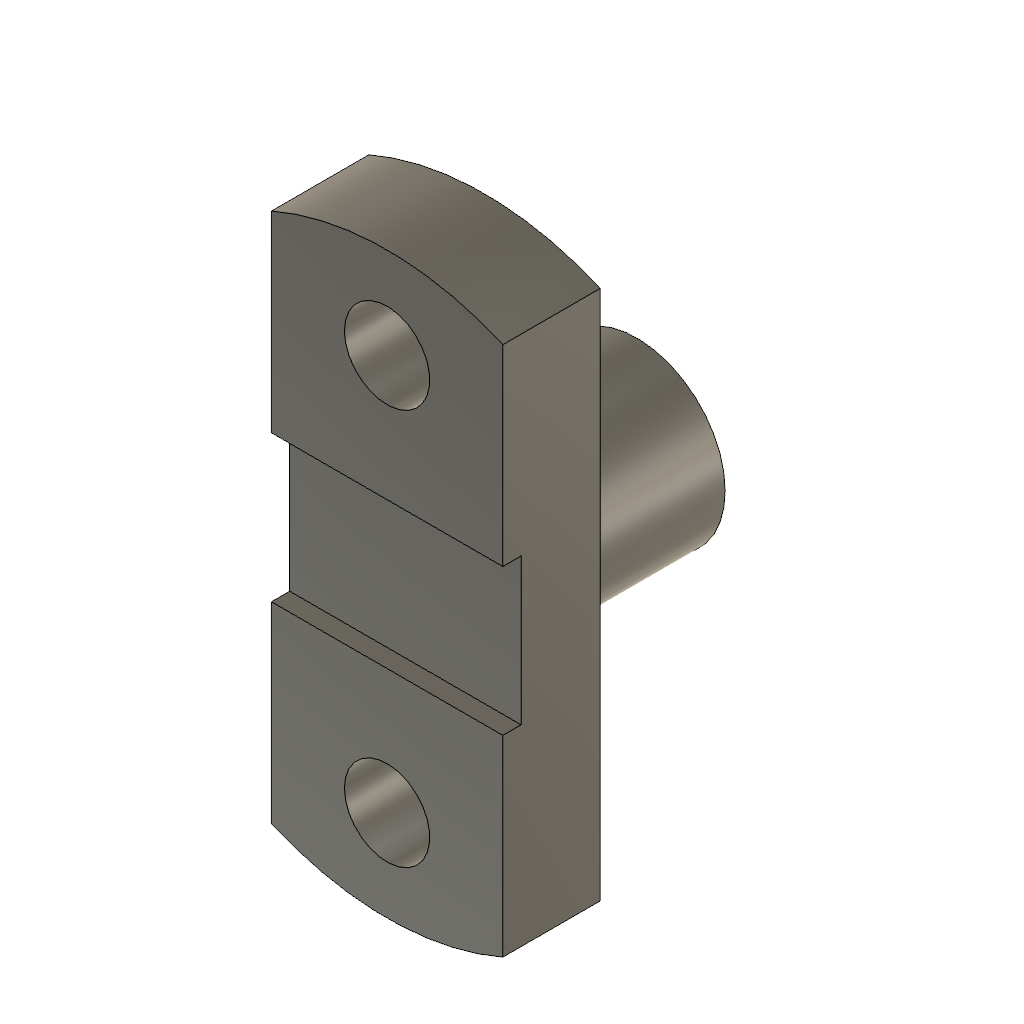
assembled one (Autodesk Fusion 360 archive; units mm, degrees)
design "rodend"
part number: 2026-10-08-14-04-04-450
Autodesk Fusion 360 part; units mm, degrees
sketch "Sketch1" plane through (0, 0, 0) normal (0, 1, 0) x (1, 0, 0)
  line L0 (0, 0) -> (76, 0)
  line L1 (76, 0) -> (76, -190)
  line L2 (76, -190) -> (0, -190)
  line L3 (0, -190) -> (0, 0)
  line L4 (0, -190) -> (38, -190)
  line L5 (38, -190) -> (38, -160)
  line L6 (38, -160) -> (0, -160)
  line L7 (0, -160) -> (0, -190)
  circle A0 centre (38, -160) radius 14
  line L8 (38, -160) -> (38, -30)
  circle A1 centre (38, -30) radius 14
  dimension "d1" = 76
  dimension "d2" = 190
  dimension "d3" = 38
  dimension "d4" = 30
  dimension "d5" = 28
  dimension "d6" = 130
  dimension "d7" = 28
  constraint horizontal L0
  constraint vertical L1
  constraint horizontal L2
  constraint vertical L3
  constraint coincident L0.start L3.end
  constraint horizontal L4
  constraint vertical L5
  constraint horizontal L6
  constraint vertical L7
  constraint coincident L5.end L6.start
  constraint perpendicular L6 L8
  constraint coincident L8.end A1.centre
  measures "d1" distance of L0.start L0.end
  measures "d2" distance of L0.start L2.end
  measures "d3" distance of L2.end L4.end
  measures "d4" distance of L2.end L6.end
  measures "d5" diameter of A0
  measures "d6" distance of L5.end L8.end
  measures "d7" diameter of A1
extrude "Extrude1" add sketch "Sketch1" along normal blind 32 contours L0 L1 L2 L3 L5 L6 A0 | L2 L3 L4 L5 L6 L7 A0
sketch "Sketch2" plane through (76, 0, 0) normal (1, 0, 0) x (0, 1, 0)
  line L0 (0, 190) -> (0, 0)
  line L1 (0, 0) -> (32, 0)
  line L2 (32, 0) -> (32, 190)
  line L3 (32, 190) -> (0, 190)
  line L4 (0, 190) -> (0, 95)
  line L5 (6, 71) -> (-6, 71)
  line L6 (-6, 71) -> (-6, 119)
  line L7 (-6, 119) -> (6, 119)
  line L8 (6, 119) -> (6, 71)
  line L9 (6, 71) -> (-6, 119) construction
  line L10 (-6, 71) -> (6, 119) construction
  point P0 (0, 95)
  dimension "d10" = 95
  dimension "d11" = 12
  dimension "d12" = 48
  constraint coincident L0.start L3.end
  constraint perpendicular L3 L4
  constraint horizontal L5
  constraint perpendicular L5 L6
  constraint parallel L5 L7
  constraint parallel L6 L8
  constraint coincident L9 P0
  constraint coincident L10 P0
  constraint coincident P0 L4.end
  measures "d10" distance of L0.start P0
  measures "d11" distance of L6.end L7.end
  measures "d12" distance of L5.end L6.end
extrude "Extrude2" cut sketch "Sketch2" against normal blind 170 contours L0 L4 L5 L7 L8
sketch "Sketch3" plane through (0, 32, 0) normal (0, 1, 0) x (-1, 0, 0)
  circle A0 centre (-38, 160) radius 14
  circle A1 centre (-38, 30) radius 14
  line L0 (0, 0) -> (0, 190)
  line L1 (0, 190) -> (-76, 190)
  line L2 (-76, 190) -> (-76, 0)
  line L3 (-76, 0) -> (0, 0)
  line L4 (-76, 190) -> (-38, 190)
  line L5 (-76, 95) -> (-76, 190)
  circle A2 centre (-38, 95) radius 29
  dimension "d15" = 38
  dimension "d16" = 95
  dimension "d17" = 58
  constraint horizontal L4
  constraint vertical L5
  constraint coincident L1.end L2.start
  measures "d15" distance of L1.end L4.end
  measures "d16" distance of L1.end L5.start
  measures "d17" diameter of A2
extrude "Extrude3" add sketch "Sketch3" along normal blind 50 contours A2
sketch "Sketch4" plane through (0, 0, 0) normal (0, -1, 0) x (1, 0, 0)
  line L0 (0, 119) -> (76, 119)
  line L1 (76, 119) -> (76, 190)
  line L2 (76, 190) -> (0, 190)
  line L3 (0, 190) -> (0, 119)
  circle A0 centre (38, 160) radius 14
  line L4 (0, 190) -> (38, 190)
  line L5 (38, 190) -> (38, 95)
  line L6 (38, 95) -> (0, 95)
  line L7 (0, 95) -> (0, 190)
  circle A1 centre (38, 95) radius 95
  dimension "d20" = 38
  dimension "d21" = 95
  dimension "d22" = 190
  constraint horizontal L4
  constraint vertical L5
  constraint horizontal L6
  constraint vertical L7
  constraint coincident L2.end L3.start
  constraint coincident L5.end L6.start
  measures "d20" distance of L2.end L4.end
  measures "d21" distance of L2.end L6.end
  measures "d22" diameter of A1
extrude "Extrude4" cut sketch "Sketch4" against normal blind 170 contours L2 L3 L4 L7 A1 | L1 L2 A1
sketch "Sketch5" plane through (0, 0, 0) normal (0, -1, 0) x (1, 0, 0)
  circle A0 centre (38, 30) radius 14
  line L0 (76, 71) -> (0, 71)
  line L1 (0, 71) -> (0, 0)
  line L2 (0, 0) -> (76, 0)
  line L3 (76, 0) -> (76, 71)
  line L4 (0, 0) -> (38, 0)
  line L5 (38, 0) -> (38, 95)
  line L6 (38, 95) -> (0, 95)
  line L7 (0, 95) -> (0, 0)
  circle A1 centre (38, 95) radius 95
  dimension "d25" = 38
  dimension "d26" = 95
  dimension "d27" = 190
  constraint horizontal L4
  constraint vertical L5
  constraint horizontal L6
  constraint vertical L7
  constraint coincident L1.end L2.start
  constraint coincident L5.end L6.start
  measures "d25" distance of L1.end L4.end
  measures "d26" distance of L1.end L6.end
  measures "d27" diameter of A1
extrude "Extrude5" cut sketch "Sketch5" against normal blind 490 contours L2 L3 A1 | L1 L2 L4 L7 A1

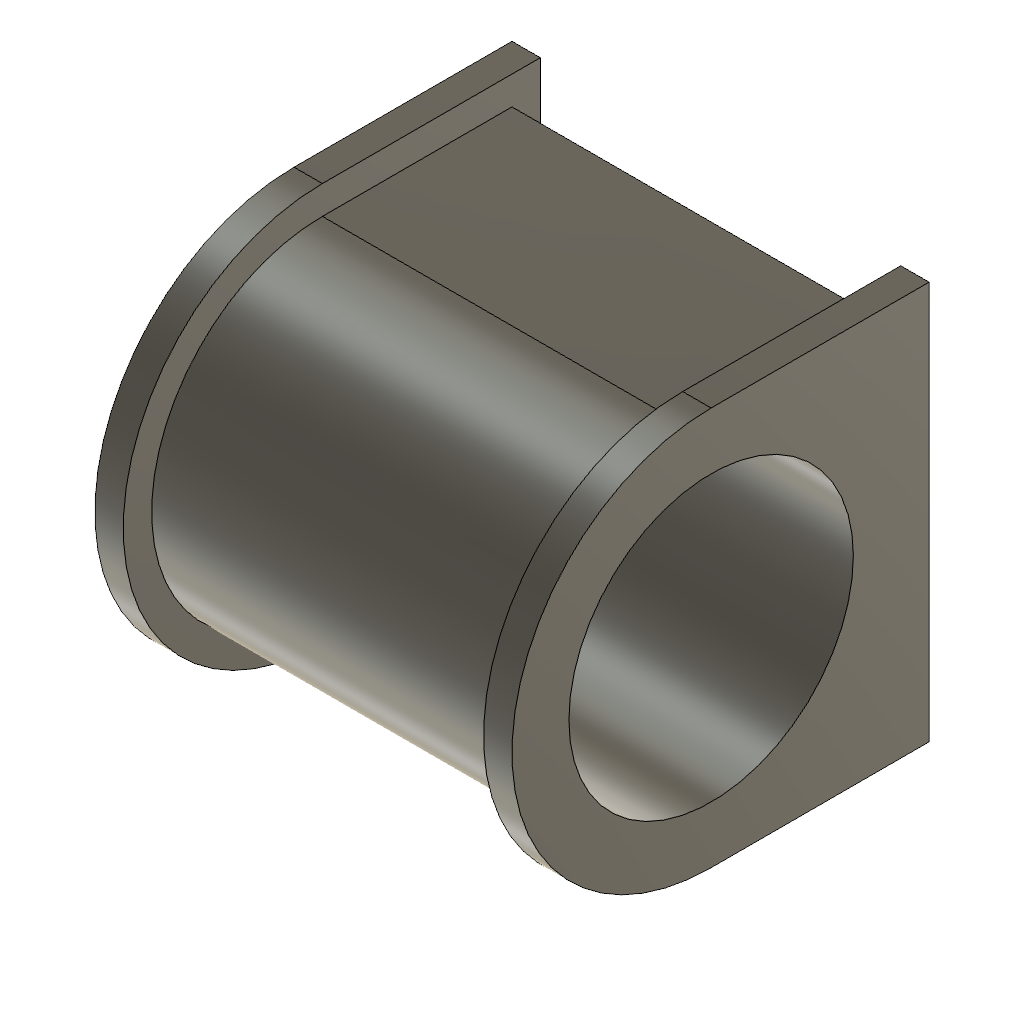
design "brasses"
part number: 2026-10-08-14-32-37-990
Autodesk Fusion 360 part; units mm, degrees
sketch "Sketch1" plane through (0, 0, 0) normal (1, 0, 0) x (0, 1, 0)
  circle A0 centre (0, 0) radius 30
  line L0 (0, 36) -> (40, 36)
  line L1 (0, 42) -> (46, 42)
  line L2 (0, -36) -> (40, -36)
  line L3 (0, -42) -> (46, -42)
  line L4 (40, 36) -> (40, -36)
  line L5 (46, 42) -> (46, -42)
  arc A1 (0, 36) -> (0, -36) centre (0, 0) ccw
  arc A2 (0, 42) -> (0, -42) centre (0, 0) ccw
  dimension "d1" = 60
  dimension "d2" = 72
  dimension "d3" = 84
  dimension "d4" = 40
  dimension "d5" = 46
  dimension "d6" = 40
  dimension "d7" = 46
  constraint coincident A0.centre A1.centre
  constraint horizontal L0
  constraint horizontal L1
  constraint horizontal L2
  constraint horizontal L3
  constraint tangent L0 A1
  constraint tangent L1 A2
  constraint tangent L2 A1
  constraint tangent L3 A2
  measures "d1" diameter of A0
  measures "d2" diameter of A1
  measures "d3" diameter of A2
  measures "d4" distance of L0.start L0.end
  measures "d5" distance of L1.start L1.end
  measures "d6" distance of L2.start L2.end
  measures "d7" distance of L3.start L3.end
extrude "Extrude1" add sketch "Sketch1" along normal blind 76 contours L0 L2 L4 A1 makes body 1
sketch "Sketch2" plane through (76, 0, 0) normal (1, 0, 0) x (0, 1, 0)
  circle A0 centre (0, 0) radius 30
  line L0 (40, 36) -> (0, 36)
  arc A1 (0, 36) -> (0, -36) centre (0, 0) ccw
  line L1 (0, -36) -> (40, -36)
  line L2 (40, -36) -> (40, 36)
  line L3 (0, 42) -> (46, 42)
  line L4 (0, -42) -> (46, -42)
  line L5 (46, 42) -> (46, -42)
  arc A2 (0, 42) -> (0, -42) centre (0, 0) ccw
  dimension "d10" = 84
  dimension "d11" = 46
  dimension "d12" = 46
  constraint concentric A0 A2
  constraint perpendicular L2 L3
  constraint parallel L1 L4
  constraint tangent L3 A2
  constraint tangent L4 A2
  measures "d10" diameter of A2
  measures "d11" distance of L3.start L3.end
  measures "d12" distance of L4.start L4.end
extrude "Extrude2" add sketch "Sketch2" along normal blind 6 separate body contours L3 L4 L5 A2 makes body 2
extrude "Extrude3" add 1 faces at (76, 36.6667, 0) along direction (1, 0, 0) blind 6 on bodies 1 bodies 1 2
sketch "Sketch3" plane through (0, 0, 0) normal (-1, 0, 0) x (0, -1, 0)
  circle A0 centre (0, 0) radius 30
  line L0 (0, 36) -> (-40, 36)
  line L1 (-40, 36) -> (-40, -36)
  line L2 (-40, -36) -> (0, -36)
  arc A1 (0, -36) -> (0, 36) centre (0, 0) ccw
  line L3 (0, 42) -> (-46, 42)
  line L4 (-46, 42) -> (-46, -42)
  line L5 (-46, -42) -> (0, -42)
  arc A2 (0, -42) -> (0, 42) centre (0, 0) ccw
  dimension "d17" = 84
  dimension "d18" = 46
  dimension "d19" = 84
  constraint concentric A0 A2
  constraint horizontal L3
  constraint vertical L4
  constraint horizontal L5
  measures "d17" diameter of A2
  measures "d18" distance of L3.start L3.end
  measures "d19" distance of L3.start L5.end
extrude "Extrude4" add sketch "Sketch3" along normal blind 6 contours L0 L1 L2 A1 | L3 L4 L5 A2 bodies 1

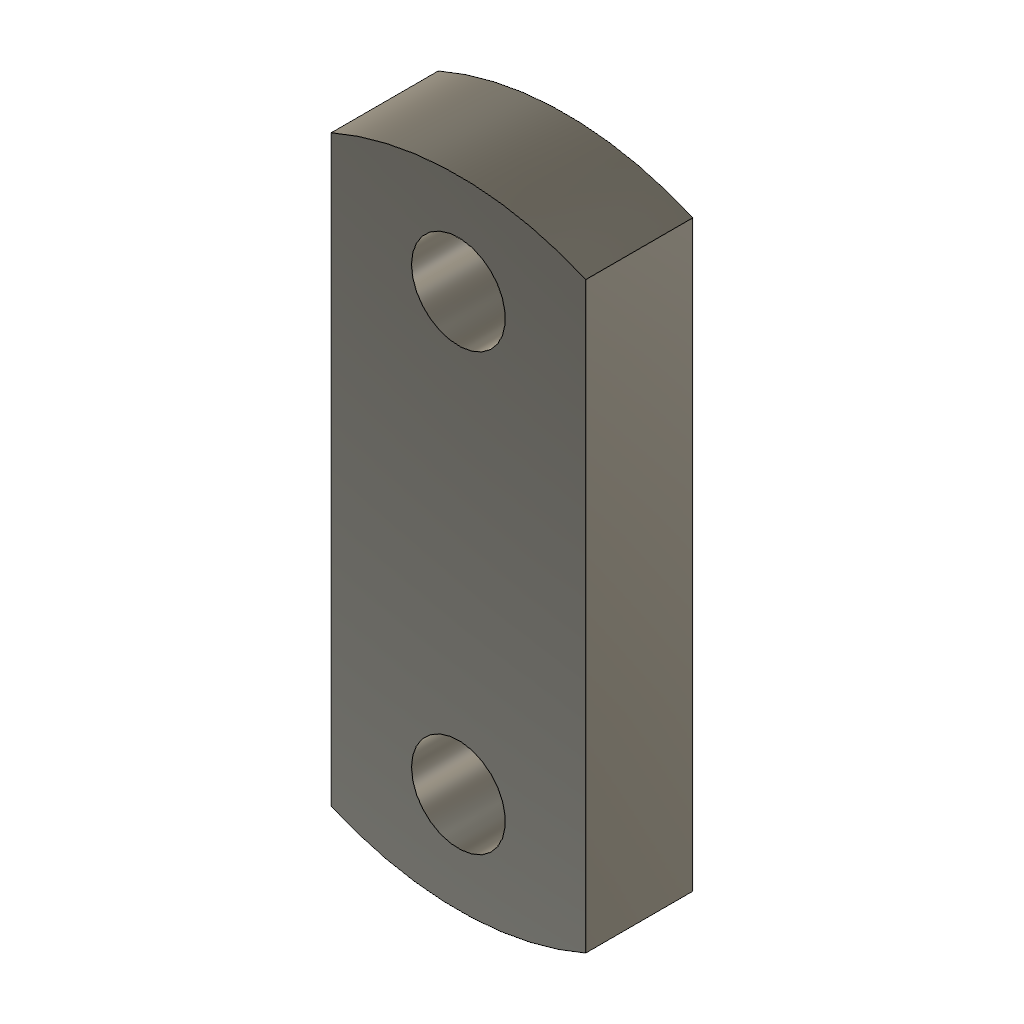
design "coverplate"
part number: 2026-10-08-13-52-12-406
Autodesk Fusion 360 part; units mm, degrees
sketch "Sketch1" plane through (0, 0, 0) normal (0, 1, 0) x (1, 0, 0)
  line L0 (0, 0) -> (76, 0)
  line L1 (76, 0) -> (76, -190)
  line L2 (76, -190) -> (0, -190)
  line L3 (0, -190) -> (0, 0)
  dimension "d1" = 76
  dimension "d2" = 190
  constraint horizontal L0
  constraint vertical L1
  constraint horizontal L2
  constraint vertical L3
  constraint coincident L0.start L3.end
  measures "d1" distance of L0.start L0.end
  measures "d2" distance of L0.start L2.end
extrude "Extrude1" add sketch "Sketch1" along normal blind 32
sketch "Sketch2" plane through (0, 0, 0) normal (0, -1, 0) x (1, 0, 0)
  line L0 (76, 190) -> (0, 190)
  line L1 (0, 190) -> (0, 0)
  line L2 (0, 0) -> (76, 0)
  line L3 (76, 0) -> (76, 190)
  line L4 (0, 190) -> (38, 190)
  line L5 (38, 190) -> (38, 160)
  line L6 (38, 160) -> (0, 160)
  line L7 (0, 160) -> (0, 190)
  circle A0 centre (38, 160) radius 14
  line L8 (38, 160) -> (38, 30)
  circle A1 centre (38, 30) radius 14
  dimension "d5" = 38
  dimension "d6" = 30
  dimension "d7" = 28
  dimension "d8" = 130
  dimension "d9" = 28
  constraint horizontal L4
  constraint vertical L5
  constraint horizontal L6
  constraint vertical L7
  constraint coincident L0.end L1.start
  constraint coincident L5.end L6.start
  constraint perpendicular L6 L8
  constraint coincident L8.end A1.centre
  measures "d5" distance of L0.end L4.end
  measures "d6" distance of L0.end L6.end
  measures "d7" diameter of A0
  measures "d8" distance of L5.end L8.end
  measures "d9" diameter of A1
extrude "Extrude2" cut sketch "Sketch2" against normal blind 250 contours L5 A0 L8 | L5 L6 A0 | L6 A0 L8 | A1
sketch "Sketch3" plane through (0, 0, 0) normal (0, -1, 0) x (1, 0, 0)
  circle A0 centre (38, 160) radius 14
  circle A1 centre (38, 30) radius 14
  line L0 (76, 190) -> (0, 190)
  line L1 (0, 190) -> (0, 0)
  line L2 (0, 0) -> (76, 0)
  line L3 (76, 0) -> (76, 190)
  line L4 (0, 190) -> (38, 190)
  line L5 (38, 190) -> (38, 95)
  line L6 (38, 95) -> (0, 95)
  line L7 (0, 95) -> (0, 190)
  circle A2 centre (38, 95) radius 95
  dimension "d12" = 38
  dimension "d13" = 95
  dimension "d14" = 190
  constraint horizontal L4
  constraint vertical L5
  constraint horizontal L6
  constraint vertical L7
  constraint coincident L0.end L1.start
  constraint coincident L5.end L6.start
  measures "d12" distance of L0.end L4.end
  measures "d13" distance of L0.end L6.end
  measures "d14" diameter of A2
extrude "Extrude3" cut sketch "Sketch3" against normal blind 220 contours L0 L1 L4 L7 A2 | L0 L3 A2 | L2 L3 A2 | L1 L2 A2

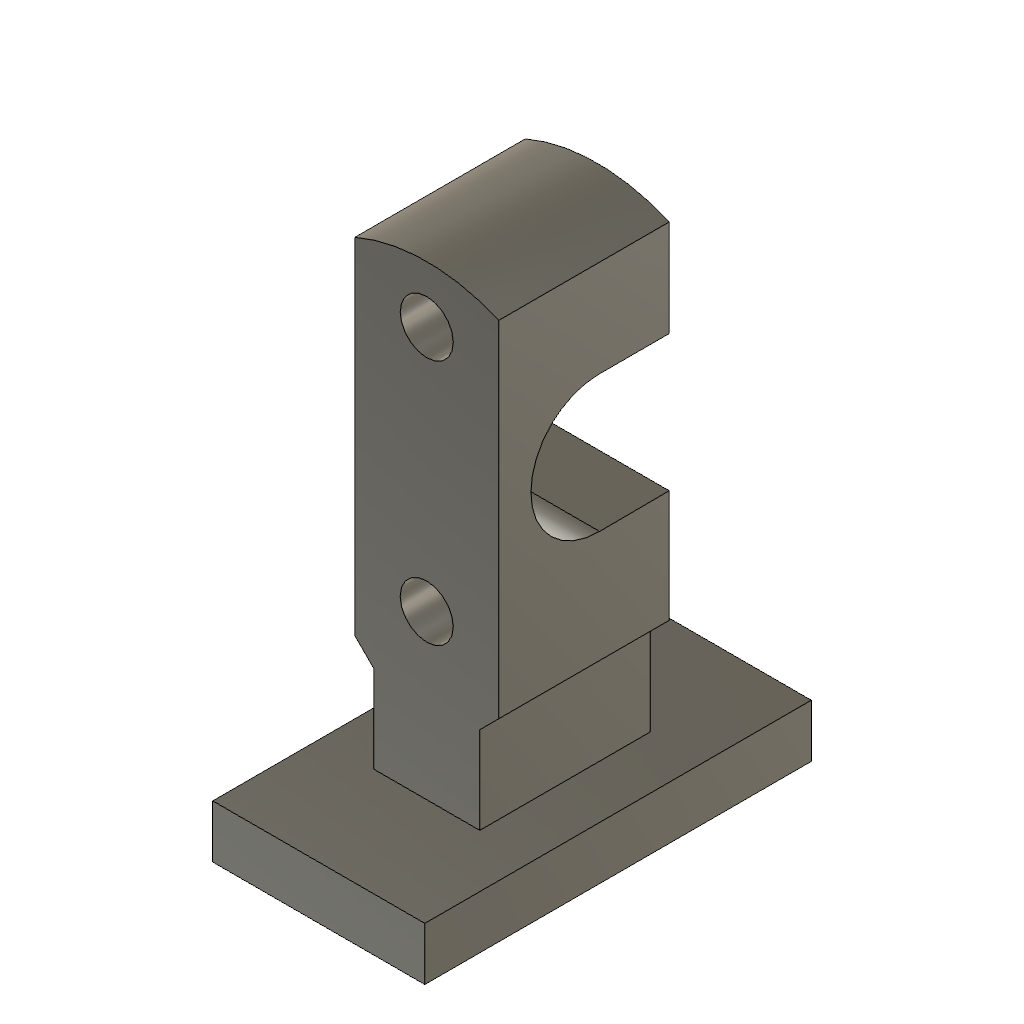
design "body"
part number: 2026-10-08-13-23-09-316
Autodesk Fusion 360 part; units mm, degrees
sketch "Sketch1" plane through (0, 0, 0) normal (1, 0, 0) x (0, 1, 0)
  line L0 (0, 0) -> (90, 0)
  line L1 (90, 190) -> (0, 190)
  line L2 (0, 190) -> (0, 0)
  line L3 (90, 0) -> (90, 59.2435)
  line L4 (90, 95) -> (89, 95)
  line L5 (53, 131) -> (90, 131)
  line L6 (53.2376, 59.0008) -> (90, 59.2435)
  arc A0 (53, 131) -> (53.2376, 59.0008) centre (53, 95) ccw
  line L7 (90, 0) -> (90, 59.2435)
  line L8 (90, 131) -> (90, 190)
  line L9 (0, 0) -> (90, 0)
  line L10 (90, 0) -> (90, -56)
  line L11 (90, -56) -> (0, -56)
  line L12 (0, -56) -> (0, 0)
  line L13 (90, -56) -> (147, -56)
  line L14 (147, -56) -> (147, -84)
  line L15 (147, -84) -> (90, -84)
  line L16 (0, -56) -> (-57, -56)
  line L17 (-57, -56) -> (-57, -84)
  line L18 (-57, -84) -> (0, -84)
  line L19 (-57, -56) -> (147, -56)
  line L20 (147, -56) -> (147, -84)
  line L21 (147, -84) -> (-57, -84)
  line L22 (-57, -84) -> (-57, -56)
  dimension "d1" = 90
  dimension "d2" = 190
  dimension "d3" = 95
  dimension "d4" = 37
  dimension "d5" = 72
  dimension "d6" = 90
  dimension "d7" = 56
  dimension "d8" = 57
  dimension "d9" = 28
  dimension "d10" = 57
  dimension "d11" = 28
  constraint horizontal L0
  constraint vertical L7
  constraint horizontal L1
  constraint vertical L2
  constraint coincident L0.start L2.end
  constraint perpendicular L0 L3
  constraint perpendicular L4 L7
  constraint perpendicular L5 L8
  constraint tangent L5 A0
  constraint tangent L6 A0
  constraint collinear L7 L8
  constraint horizontal L9
  constraint vertical L10
  constraint horizontal L11
  constraint vertical L12
  constraint horizontal L13
  constraint vertical L14
  constraint horizontal L15
  constraint horizontal L16
  constraint vertical L17
  constraint horizontal L18
  constraint horizontal L19
  constraint vertical L20
  constraint horizontal L21
  constraint vertical L22
  measures "d1" distance of L0.start L0.end
  measures "d2" distance of L0.start L1.end
  measures "d3" distance of L0.end L4.start
  measures "d4" distance of L4.start A0.centre
  measures "d5" diameter of A0
  measures "d6" distance of L0.start L0.end
  measures "d7" distance of L0.start L11.end
  measures "d8" distance of L10.end L13.end
  measures "d9" distance of L10.end L15.end
  measures "d10" distance of L11.end L16.end
  measures "d11" distance of L11.end L18.end
extrude "Extrude1" add sketch "Sketch1" along normal blind 76 contours L0 L1 L2 L3 L5 L6 A0 L7 L8 L9
sketch "Sketch2" plane through (0, 0, 0) normal (0, -1, 0) x (1, 0, 0)
  line L0 (0, 190) -> (0, 0)
  line L1 (0, 0) -> (76, 0)
  line L2 (76, 0) -> (76, 190)
  line L3 (76, 190) -> (0, 190)
  line L4 (76, 0) -> (66, -10)
  line L5 (76, 0) -> (52.0292, 0) construction
  line L6 (0, 0) -> (10, -10)
  line L7 (0, 0) -> (34.0699, 0) construction
  line L8 (0, 0) -> (10, 0)
  line L9 (10, 0) -> (10, 10)
  line L10 (10, 10) -> (0, 10)
  line L11 (0, 10) -> (0, 0)
  line L12 (10, 0) -> (66, 0)
  line L13 (66, -10) -> (66, -56)
  line L14 (66, -56) -> (10, -56)
  line L15 (10, -56) -> (10, -10)
  dimension "d14" = 45
  dimension "d15" = 45
  dimension "d16" = 10
  dimension "d17" = 10
  dimension "d18" = 56
  dimension "d19" = 56
  constraint horizontal L5
  constraint coincident L1.end L2.start
  constraint horizontal L7
  constraint coincident L0.end L1.start
  constraint horizontal L8
  constraint vertical L9
  constraint horizontal L10
  constraint vertical L11
  constraint horizontal L12
  constraint vertical L13
  constraint horizontal L14
  constraint vertical L15
  measures "d14" angle of L4 L5
  measures "d15" angle of L6 L7
  measures "d16" distance of L0.end L8.end
  measures "d17" distance of L0.end L10.end
  measures "d18" distance of L8.end L12.end
  measures "d19" distance of L8.end L14.end
extrude "Extrude2" add sketch "Sketch2" against normal blind 90 contours L1 L4 L6 L8 L12 L13 L14 L15
sketch "Sketch3" plane through (66, 0, 0) normal (1, 0, 0) x (0, 1, 0)
  line L0 (0, -10) -> (0, -56)
  line L1 (0, -56) -> (90, -56)
  line L2 (90, -56) -> (90, -10)
  line L3 (90, -10) -> (0, -10)
  line L4 (0, -56) -> (-57, -56)
  line L5 (-57, -56) -> (-57, -84)
  line L6 (-57, -84) -> (0, -84)
  line L7 (-57, -56) -> (147, -56)
  line L8 (147, -56) -> (147, -84)
  line L9 (147, -84) -> (-57, -84)
  line L10 (-57, -84) -> (-57, -56)
  dimension "d22" = 57
  dimension "d23" = 28
  dimension "d24" = 204
  dimension "d25" = 28
  constraint horizontal L4
  constraint vertical L5
  constraint horizontal L6
  constraint coincident L0.end L1.start
  constraint horizontal L7
  constraint vertical L8
  constraint horizontal L9
  constraint vertical L10
  measures "d22" distance of L0.end L4.end
  measures "d23" distance of L0.end L6.end
  measures "d24" distance of L4.end L7.end
  measures "d25" distance of L4.end L5.end
extrude "Extrude3" add sketch "Sketch3" along normal blind 28 and the other way blind 84 contours L1 L4 L5 L6 L7 L8 L9 L10
sketch "Sketch4" plane through (0, 0, 0) normal (0, -1, 0) x (1, 0, 0)
  line L0 (0, 190) -> (0, 0)
  line L1 (0, 0) -> (10, -10)
  line L2 (10, -10) -> (10, -56)
  line L3 (10, -56) -> (66, -56)
  line L4 (66, -56) -> (66, -10)
  line L5 (66, -10) -> (76, 0)
  line L6 (76, 0) -> (76, 190)
  line L7 (76, 190) -> (0, 190)
  line L8 (0, 190) -> (38, 190)
  line L9 (38, 190) -> (38, 160)
  line L10 (38, 160) -> (0, 160)
  line L11 (0, 160) -> (0, 190)
  circle A0 centre (38, 160) radius 14
  line L12 (38, 160) -> (38, 30)
  circle A1 centre (38, 30) radius 14
  dimension "d30" = 38
  dimension "d31" = 30
  dimension "d32" = 28
  dimension "d33" = 130
  dimension "d34" = 28
  constraint horizontal L8
  constraint vertical L9
  constraint horizontal L10
  constraint vertical L11
  constraint coincident L0.start L7.end
  constraint coincident L9.end L10.start
  constraint perpendicular L10 L12
  constraint coincident L12.end A1.centre
  measures "d30" distance of L0.start L8.end
  measures "d31" distance of L0.start L10.end
  measures "d32" diameter of A0
  measures "d33" distance of L9.end L12.end
  measures "d34" diameter of A1
extrude "Extrude4" cut sketch "Sketch4" against normal blind 325 contours L9 L10 A0 | L10 A0 L12 | L9 A0 L12 | A1
sketch "Sketch5" plane through (0, 0, 0) normal (0, -1, 0) x (1, 0, 0)
  circle A0 centre (38, 160) radius 14
  circle A1 centre (38, 30) radius 14
  line L0 (0, 190) -> (0, 0)
  line L1 (0, 0) -> (10, -10)
  line L2 (10, -10) -> (10, -56)
  line L3 (10, -56) -> (66, -56)
  line L4 (66, -56) -> (66, -10)
  line L5 (66, -10) -> (76, 0)
  line L6 (76, 0) -> (76, 190)
  line L7 (76, 190) -> (0, 190)
  line L8 (0, 190) -> (0, 95)
  line L9 (0, 95) -> (38, 95)
  circle A2 centre (38, 95) radius 95
  dimension "d37" = 95
  dimension "d38" = 38
  dimension "d39" = 190
  constraint coincident L0.start L7.end
  constraint perpendicular L7 L8
  constraint perpendicular L6 L9
  constraint coincident L9.end A2.centre
  measures "d37" distance of L0.start L8.end
  measures "d38" distance of L8.end L9.end
  measures "d39" diameter of A2
extrude "Extrude5" cut sketch "Sketch5" against normal blind 175 contours L0 L7 L8 A2 | L6 L7 A2

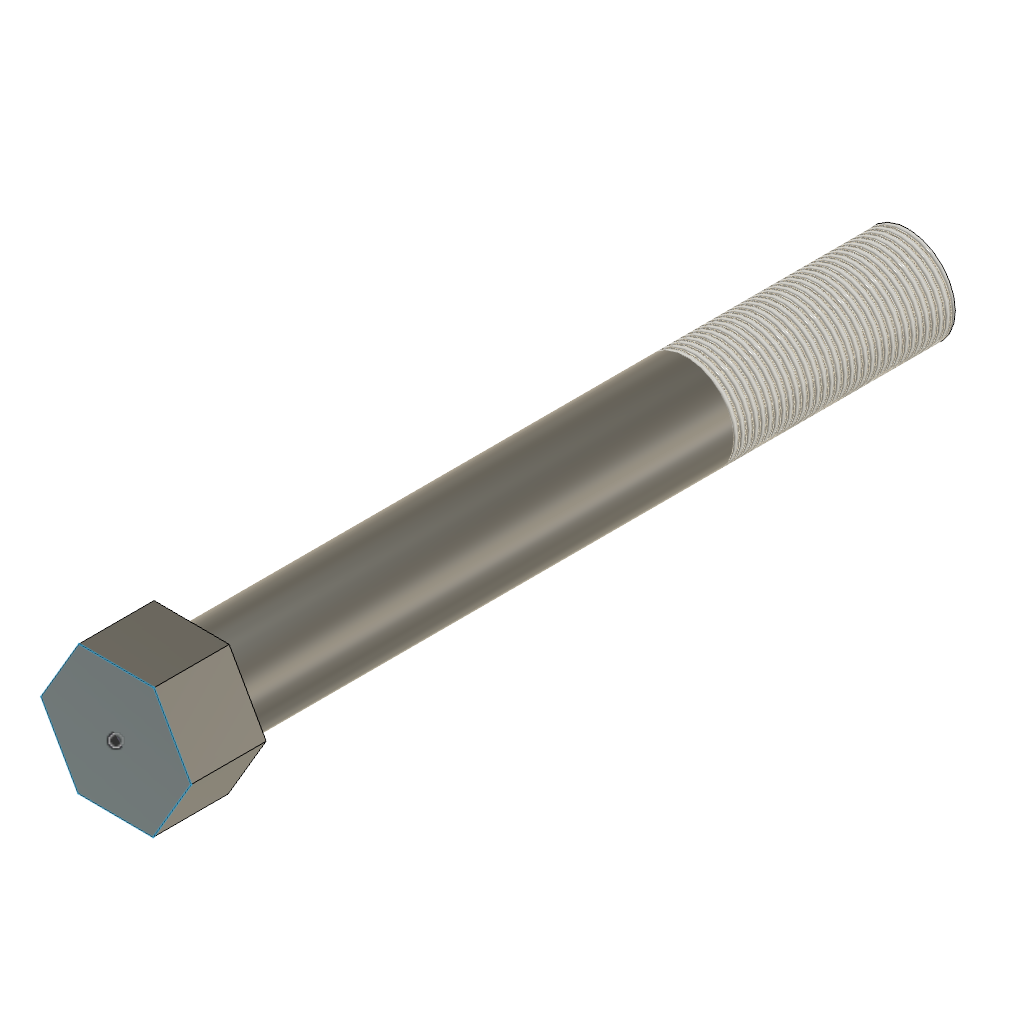
design "bolt"
part number: 2026-10-08-14-24-53-336
Autodesk Fusion 360 part; units mm, degrees
sketch "Sketch1" plane through (0, 0, 0) normal (0, 1, 0) x (1, 0, 0)
  line L0 (21.9994, 0.1571) -> (10.8636, 19.1306)
  line L1 (10.8636, 19.1306) -> (-11.1358, 18.9735)
  line L2 (-11.1358, 18.9735) -> (-21.9994, -0.1571)
  line L3 (-21.9994, -0.1571) -> (-10.8636, -19.1306)
  line L4 (-10.8636, -19.1306) -> (11.1358, -18.9735)
  line L5 (11.1358, -18.9735) -> (21.9994, 0.1571)
  dimension "d1" = 22
  measures "d1" distance of L0.start origin
extrude "Extrude1" add sketch "Sketch1" along normal blind 22
sketch "Sketch3" plane through (0, 22, 0) normal (0, 1, 0) x (-1, 0, 0)
  line L0 (-11.1358, 18.9735) -> (-21.9994, -0.1571)
  line L1 (-21.9994, -0.1571) -> (-10.8636, -19.1306)
  line L2 (-10.8636, -19.1306) -> (11.1358, -18.9735)
  line L3 (11.1358, -18.9735) -> (21.9994, 0.1571)
  line L4 (21.9994, 0.1571) -> (10.8636, 19.1306)
  line L5 (10.8636, 19.1306) -> (-11.1358, 18.9735)
  circle A0 centre (0, 0) radius 14
  dimension "d11" = 28
  constraint coincident A0.centre origin
  measures "d11" diameter of A0
extrude "Extrude4" add sketch "Sketch3" along normal blind 210 contours A0
thread "Thread2" "ISO Metric profile 28.0 M28x2 M28x2 6g" major diameter 27.822 minor diameter 25.5289 pitch 2 angle 60 resizes the face on face at (-13.9304, 162, -1.3939) from (0, 167, 0) to (0, 232, 0)

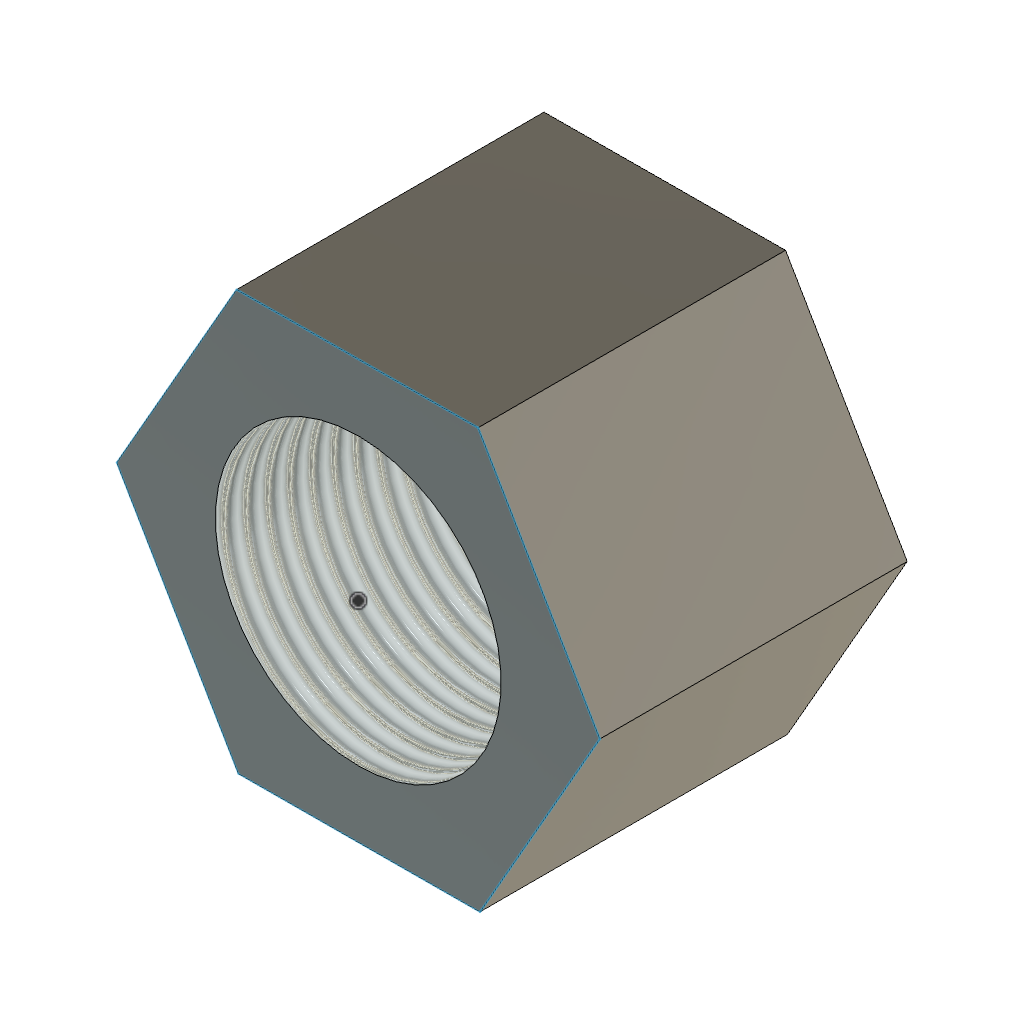
design "nut"
part number: 2026-10-08-14-31-20-378
Autodesk Fusion 360 part; units mm, degrees
sketch "Sketch1" plane through (0, 0, 0) normal (0, 1, 0) x (1, 0, 0)
  line L0 (11.0852, 19.0031) -> (-10.9146, 19.1016)
  line L1 (-10.9146, 19.1016) -> (-21.9998, 0.0985)
  line L2 (-21.9998, 0.0985) -> (-11.0852, -19.0031)
  line L3 (-11.0852, -19.0031) -> (10.9146, -19.1016)
  line L4 (10.9146, -19.1016) -> (21.9998, -0.0985)
  line L5 (21.9998, -0.0985) -> (11.0852, 19.0031)
  dimension "d1" = 22
  measures "d1" distance of L0.start origin
extrude "Extrude2" add sketch "Sketch1" along normal blind 28
hole "Hole2" at (0, 0, 0) direction (0, 1, 0) diameter 26.022 depth 125 tip angle 118
thread "Thread2" "ISO Metric profile 28.0 M28x2 M28x2 6H" thread offset 0 thread depth 7.4
